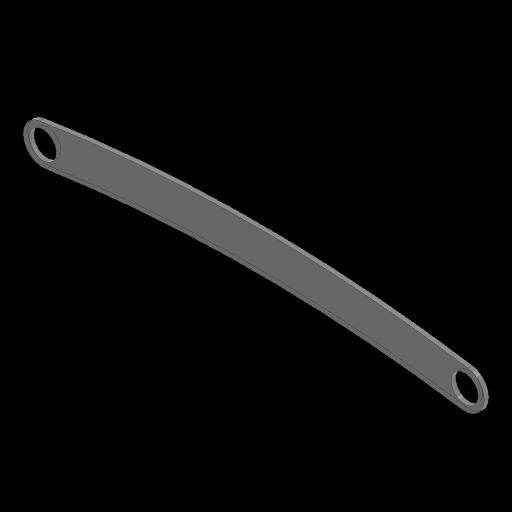
# Autodesk Inventor part: Part1
Saved by Autodesk Inventor 2027.1 (Build 311270010, 270A)
## iProperties
Created: 2026-11-13
Part Number: Part1
Material: Polycarbonate, Clear
Document SubType Name: Modeling
Designer: Stanley Ruangsuwan
Density: 1.2 g/cm^3
Appearance: Polycarbonate - Clear
Author: Stanley Ruangsuwan
Autodesk Inventor part; units mm, degrees
ref_plane "YZ Plane" through (0, 0, 0) normal (1, 0, 0) x (0, 1, 0)
ref_plane "XZ Plane" through (0, 0, 0) normal (0, 1, 0) x (-1, 0, 0)
ref_plane "XY Plane" through (0, 0, 0) normal (0, 0, 1) x (1, 0, 0)
sketch "Sketch1" plane through (0, 0, 0) normal (0, 0, 1) x (1, 0, 0)
  line L0 (0, 0) -> (443.992, 0) construction
  line L1 (0, 0) -> (443.992, 0) construction
  circle A0 centre (0, 0) radius 20.6375
  circle A1 centre (443.992, 0) radius 20.6375
  arc A2 (447.1778, 20.3901) -> (-3.1858, 20.3901) centre (221.996, -1420.8431) ccw
  arc A3 (440.8951, -20.4038) -> (3.0969, -20.4038) centre (221.996, -1462.6046) ccw
  circle A4 centre (0, 0) radius 14.2875
  circle A5 centre (443.992, 0) radius 14.2875
  dimension "d0" = 443.992
  dimension "d2" = 41.275
  dimension "d5" = 1458.7186
  dimension "d6" = 28.575
  constraints: 8 point on circle, 6 centre point, 4 coincident, 4 end point, 4 tangent, 2 equal radius, 2 horizontal, 1 collinear, 1 vertical alignment
  measures "d0" distance of L0.start L0.end
  measures "d2" diameter of A0
  measures "d5" radius of A3
  measures "d6" diameter of A4
extrude "Extrusion1" add sketch "Sketch1" along normal blind 4.7625
body "Solid1"
